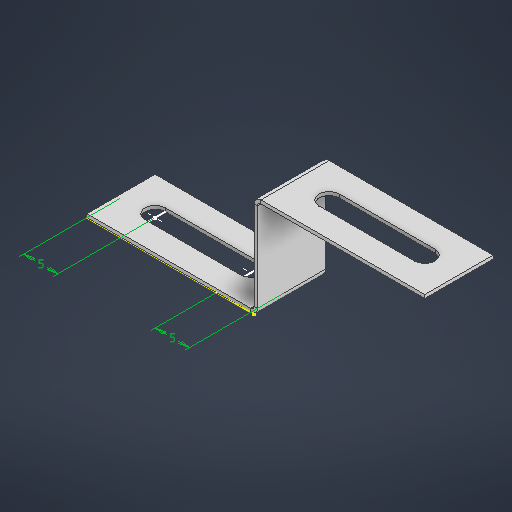
# Autodesk Inventor part: 22.10.2025-b2
Saved by Autodesk Inventor 2026.1 (Build 301233020, 233B)
## iProperties
Created: 2026-01-09
Part Number: 22.10.2025-b2
Material: Ogólny
Document SubType Name: Sheet Metal
Designer: Nitro
Density: 1 g/cm^3
Sheet Metal Rule: Domyślny_mm
Appearance: Domyślna
Flat Pattern Width: 1 cm
Flat Pattern Length: 6.32619 cm
Flat Pattern Area: 6.32619 cm^2
Sheet Metal Width: 10,000 mm
Sheet Metal Length: 63,262 mm
Sheet Metal Area: 632,619 mm^2
Author: Nitro
Autodesk Inventor part; units mm, degrees
ref_plane "YZ Plane" through (0, 0, 0) normal (1, 0, 0) x (0, 1, 0)
ref_plane "XZ Plane" through (0, 0, 0) normal (0, 1, 0) x (-1, 0, 0)
ref_plane "XY Plane" through (0, 0, 0) normal (0, 0, 1) x (1, 0, 0)
sketch "Szkic1" plane through (0, 0, 0) normal (1, 0, 0) x (0, 1, 0)
  line L0 (0, 0) -> (-15, 0)
  line L1 (-15, 0) -> (-15, -10)
  line L2 (-15, -10) -> (0, -10)
  line L3 (0, -10) -> (0, 0)
  dimension "d0" = 15
  dimension "d1" = 10
  measures "d0" distance of L2.end L1.end
  measures "d1" distance of L1.end L0.end
extrude "Płyta1" add sketch "Szkic1" along normal blind 0.5
sketch "Szkic2" plane through (0.5, -14.5, 0) normal (0, -1, 0) x (1, 0, 0)
  line L0 (0, -10) -> (0, 0)
  line L1 (0, 0) -> (-25, 0)
  line L2 (-25, 0) -> (-25, -10)
  line L3 (-25, -10) -> (0, -10)
  constraints: 6 end point, 1 horizontal, 1 perpendicular, 1 vertical
edge flange "Kołnierz1" height 25 angle 90 thickness 0.5 bend radius 0.5 thickness toward (0, -1, 0) relief tear relief width 0.5 relief depth 0.25 corner gap 0.5 corner form 0 edges at (0, -15, -5) (0.5, 0, -5) wall of the first edge with corners at (0.5, -14.5, -10) (0.5, -14.5, 0) (-24.5, -14.5, 0) (-24.5, -14.5, -10)
bend "Zagięcie1"
corner "Narożnik1"
sketch "Szkic3" plane through (-24.5, -15, -10) normal (0, -1, 0) x (1, 0, 0)
  point P0 (24.5, 10)
sketch "Szkic4" plane through (-24.5, -15, -10) normal (0, -1, 0) x (1, 0, 0)
  line L0 (24, 0) -> (24, 10) projected
  line L1 (0, 10) -> (24, 10) projected
  line L2 (0, 0) -> (0, 10) projected
  line L3 (24, 0) -> (0, 0) projected
  line L4 (5, 10) -> (5, 0)
  line L5 (19, 10) -> (19, 0)
  point P0 (24.5, 10)
  point P1 (24, 5)
  point P2 (0, 5)
  point P3 (5, 5)
  point P4 (5, 5)
  point P5 (19, 5)
  dimension "d13" = 5
  dimension "d14" = 5
  constraints: 4 end point, 4 midpoint, 4 point on line, 2 perpendicular, 1 coincident
  measures "d13" distance from line of point (24, 5) L5
  measures "d14" distance of point (0, 5) point (5, 5)
sketch "Szkic5" plane through (-24.5, -15, -10) normal (0, -1, 0) x (1, 0, 0)
  line L0 (5, 5) -> (19, 5) construction
  line L1 (5, 3.5) -> (19, 3.5)
  line L2 (19, 6.5) -> (5, 6.5)
  arc A0 (5, 6.5) -> (5, 3.5) centre (5, 5) ccw
  arc A1 (19, 3.5) -> (19, 6.5) centre (19, 5) ccw
  point P0 (24.5, 10)
  point P1 (12, 5)
  dimension "d15" = 3
  constraints: 8 end point, 4 point on circle, 4 tangent, 2 centre point, 1 horizontal, 1 midpoint, 1 parallel
  measures "d15" diameter of A1
sketch "Szkic6" plane through (25, -0.5, -10) normal (0, -1, 0) x (1, 0, 0)
  line L0 (-24, 10) -> (-24, 0) projected
  line L1 (-24, 0) -> (0, 0) projected
  line L2 (0, 0) -> (0, 10) projected
  line L3 (-24, 10) -> (0, 10) projected
  line L4 (-24, 10) -> (0, 10) projected
  line L5 (-5, 10) -> (-5, 0)
  line L6 (-19, 10) -> (-19, 0)
  line L7 (-19, 5) -> (-5, 5) construction
  line L8 (-19, 3.5) -> (-5, 3.5)
  line L9 (-5, 6.5) -> (-19, 6.5)
  arc A0 (-19, 6.5) -> (-19, 3.5) centre (-19, 5) ccw
  arc A1 (-5, 3.5) -> (-5, 6.5) centre (-5, 5) ccw
  point P0 (-25, 10)
  point P1 (0, 5)
  point P2 (-12, 5)
  dimension "d16" = 5
  dimension "d17" = 5
  dimension "d18" = 3
  constraints: 12 end point, 4 midpoint, 4 point on circle, 4 point on line, 4 tangent, 3 perpendicular, 2 centre point, 1 parallel
  measures "d16" distance between parallel lines of L6 L0
  measures "d17" distance from line of point (0, 5) L5
  measures "d18" diameter of A1
extrude "Wyciągnięcie proste1" cut sketch "Szkic5" against normal blind 10
extrude "Wyciągnięcie proste2" cut sketch "Szkic6" against normal blind 10 contours L9 L5 L8 L6 | L6 A0 | A1 L5
equation "\"d2\" = Grubość"
equation "\"d3\" = SzerokośćGięciaPodcięcia"
equation "\"d4\" = GłębokośćGięciaPodcięcia"
equation "\"d5\" = MinimalnaPozostałość"
equation "\"d6\" = PromieńPrzejścia"
equation "\"d9\" = PromieńGięcia"
equation "\"d10\" = RozmiarPodcięciaNarożnika"
equation "\"d11\" = Wielk_odstępu"
equation "\"d12\" = Rozmiar_promienia_Jacobiego"
equation "\"PromieńGięcia\" = Grubość"
equation "\"SzerokośćGięciaPodcięcia\" = Grubość"
equation "\"GłębokośćGięciaPodcięcia\" = 0.5 * Grubość"
equation "\"RozmiarPodcięciaNarożnika\" = 4 * Grubość"
equation "\"MinimalnaPozostałość\" = 2 * Grubość"
equation "\"PromieńPrzejścia\" = PromieńGięcia"
equation "\"Rozmiar_promienia_Jacobiego\" = PromieńGięcia"
equation "\"Wielk_odstępu\" = Grubość"
equation "\"Grubość\" = 0.5"
